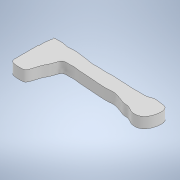
# Autodesk Inventor part: litera_L
Saved by Autodesk Inventor 2022.6 (Build 266554000, 554)
## iProperties
Created: 2024-11-30
Part Number: litera_L
Material: Generic
Document SubType Name: Modeling
Designer: Dragos Macovei
Density: 1 g/cm^3
Appearance: Default
Author: Dragos Macovei
Autodesk Inventor part; units mm, degrees
ref_plane "YZ Plane" through (0, 0, 0) normal (1, 0, 0) x (0, 1, 0)
ref_plane "XZ Plane" through (0, 0, 0) normal (0, 1, 0) x (-1, 0, 0)
ref_plane "XY Plane" through (0, 0, 0) normal (0, 0, 1) x (1, 0, 0)
sketch "Sketch1" plane through (0, 0, 0) normal (0, 1, 0) x (-1, 0, 0)
  line L0 (0, 0) -> (40, 0)
  line L1 (40, 0) -> (40, 40)
  line L2 (40, 40) -> (0, 40)
  line L3 (0, 40) -> (0, 0)
  line L4 (-163.8389, 257.6492) -> (178.1807, 257.6492) construction
  line L5 (178.1807, 257.6492) -> (178.1807, -198.3771) construction
  line L6 (178.1807, -198.3771) -> (-163.8389, -198.3771) construction
  line L7 (-163.8389, -198.3771) -> (-163.8389, 257.6492) construction
  spline S0 degree 5 poles (36.0765, 21.9365) (36.0644, 22.0566) (36.0211, 22.2505) (35.8618, 22.5239) (35.3346, 23.0272) (34.9325, 22.8637) (33.9208, 23.2594) (33.09, 22.8862) (31.8774, 23.4883) (31.2046, 21.5472) (30.7727, 18.8391) (29.3923, 18.0226) (29.5149, 14.6471) (26.9667, 15.7618) (26.5259, 15.0504) (24.5223, 15.6221) (23.2251, 15.5546) (21.8603, 15.7444) (20.7176, 15.7399) (19.4962, 15.8756) (18.2996, 15.986) (17.0454, 16.013) (15.7772, 16.1332) (14.1619, 15.781) (13.2456, 16.0752) (12.0852, 16.4348) (11.2819, 16.7402) (10.1479, 17.3282) (9.1618, 17.0694) (8.0264, 17.5431) (7.1735, 18.2405) (6.3074, 18.2843) (4.869, 18.4425) (3.777, 17.3391) (3.0493, 16.4601) (2.4307, 13.4616) (3.1995, 12.1118) (4.5184, 12.032) (5.8795, 11.9102) (7.0988, 11.5319) (8.3406, 12.6469) (10.1073, 12.2776) (11.852, 12.3736) (12.8141, 12.4565) (14.7752, 12.1362) (16.1199, 12.2916) (18.5355, 11.9357) (19.6004, 12.261) (20.7771, 12.0889) (23.15, 11.9841) (24.5985, 12.2212) (26.3894, 11.4485) (27.8477, 11.7335) (29.5958, 10.9741) (31.2848, 11.7973) (33.1948, 10.9792) (33.1789, 11.1713) (36.5928, 11.1176) (35.1268, 11.2319) (35.9196, 12.3647) (35.7726, 12.8892) (35.8712, 13.4925) (36.0201, 14.3093) (35.6533, 14.7912) (36.2589, 15.0471) (36.0056, 15.6485) (36.1047, 15.9668) (36.0646, 16.4891) (36.0818, 16.6123) (36.0745, 17.5434) (36.0776, 17.3833) (36.076, 18.2528) (36.0767, 18.3047) (36.0767, 19.3682) (36.076, 19.3109) (36.0779, 20.1241) (36.0736, 20.2852) (36.0843, 20.8808) (36.0615, 21.2679) (36.087, 21.6077) (36.0887, 21.8156) (36.0765, 21.9365) knots 0 0 0 0 0 0 0.011097 0.018982 0.0293 0.040266 0.052033 0.066368 0.082233 0.099229 0.116868 0.134138 0.150262 0.165707 0.180483 0.194939 0.209632 0.223876 0.237775 0.251808 0.266261 0.280616 0.294796 0.308631 0.3221 0.335037 0.34807 0.361063 0.373921 0.386865 0.400094 0.413776 0.4292 0.445186 0.461102 0.476964 0.492372 0.506504 0.521145 0.536334 0.551437 0.56706 0.583089 0.599405 0.615207 0.63101 0.64728 0.66352 0.679348 0.695602 0.712437 0.729133 0.745434 0.761579 0.77741 0.791159 0.803621 0.815176 0.825677 0.83561 0.845926 0.855568 0.864879 0.873743 0.881914 0.889955 0.898365 0.906132 0.914021 0.922034 0.930716 0.938784 0.947555 0.956072 0.964647 0.972973 0.981806 0.98883 1 1 1 1 1 1
  point P0 (35.4411, 22.8261)
  point P1 (34.9645, 22.9532)
  point P2 (34.1384, 23.0803)
  point P3 (33.217, 23.0803)
  point P4 (32.3274, 23.0485)
  point P5 (31.5014, 22.0953)
  point P6 (30.58, 19.2994)
  point P7 (29.6268, 17.2025)
  point P8 (28.6419, 15.4868)
  point P9 (27.2121, 15.3915)
  point P10 (26.259, 15.3279)
  point P11 (24.6704, 15.4868)
  point P12 (23.1135, 15.6139)
  point P13 (21.8109, 15.7092)
  point P14 (20.6671, 15.7727)
  point P15 (19.5233, 15.868)
  point P16 (18.3477, 15.9634)
  point P17 (17.1086, 16.0269)
  point P18 (15.6789, 16.0269)
  point P19 (14.1538, 15.9316)
  point P20 (13.1054, 16.1222)
  point P21 (12.1204, 16.4399)
  point P22 (11.2308, 16.7894)
  point P23 (10.1823, 17.1389)
  point P24 (9.1339, 17.2342)
  point P25 (8.0536, 17.6155)
  point P26 (7.1709, 18.0921)
  point P27 (6.3379, 18.2827)
  point P28 (5.1624, 18.2192)
  point P29 (4.0504, 17.552)
  point P30 (3.1925, 16.2493)
  point P31 (2.8112, 13.4216)
  point P32 (3.5102, 12.3096)
  point P33 (4.5905, 12.0236)
  point P34 (5.8296, 11.8648)
  point P35 (6.9734, 11.833)
  point P36 (8.3078, 12.2778)
  point P37 (10.1188, 12.3731)
  point P38 (11.7392, 12.3731)
  point P39 (12.9147, 12.3731)
  point P40 (14.5351, 12.246)
  point P41 (16.3461, 12.1825)
  point P42 (18.4748, 12.0872)
  point P43 (19.6186, 12.1507)
  point P44 (20.7942, 12.1189)
  point P45 (22.9229, 12.0554)
  point P46 (24.7021, 11.9919)
  point P47 (26.3543, 11.6741)
  point P48 (27.8793, 11.5153)
  point P49 (29.595, 11.3246)
  point P50 (31.5649, 11.42)
  point P51 (32.9311, 11.1658)
  point P52 (34.4561, 11.134)
  point P53 (35.6953, 11.2293)
  point P54 (35.5999, 11.4517)
  point P55 (35.727, 12.246)
  point P56 (35.8223, 12.9132)
  point P57 (35.8859, 13.5805)
  point P58 (35.8859, 14.3748)
  point P59 (35.8859, 14.7878)
  point P60 (36.0765, 15.1373)
  point P61 (36.0765, 15.6139)
  point P62 (36.0765, 16.0269)
  point P63 (36.0765, 16.4082)
  point P64 (36.0765, 16.7577)
  point P65 (36.0765, 17.3613)
  point P66 (36.0765, 17.552)
  point P67 (36.0765, 18.0285)
  point P68 (36.0765, 18.4733)
  point P69 (36.0765, 19.2041)
  point P70 (36.0765, 19.49)
  point P71 (36.0765, 20)
  point P72 (36.0765, 20.3479)
  point P73 (36.0765, 20.8245)
  point P74 (36.0765, 21.3964)
  dimension "d0" = 40
  dimension "d1" = 40
  constraints: 8 end point, 2 parallel, 1 horizontal, 1 perpendicular, 79 other
  measures "d0" distance of L2.end L1.end
  measures "d1" distance of L1.end L0.end
extrude "Extrusion1" add sketch "Sketch1" along normal blind 3 contours S0
body "Solid1"
